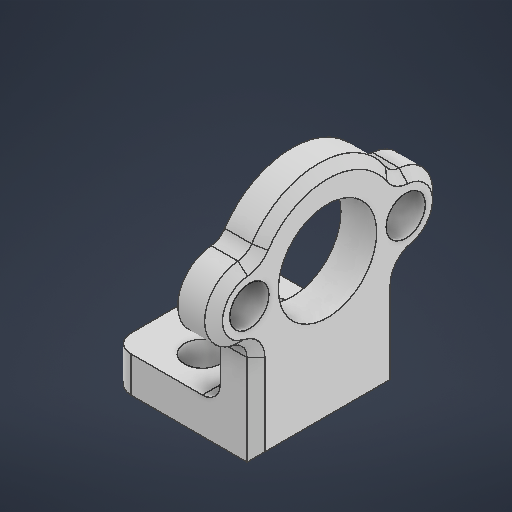
# Autodesk Inventor part: T8_holder
Saved by Autodesk Inventor 2026.2 (Build 302298010, 298A)
## iProperties
Created: 2026-04-23
Part Number: T8_holder
Material: 일반
Document SubType Name: Modeling
Designer: work
Density: 1 g/cm^3
Appearance: 기본값
Author: work
Autodesk Inventor part; units mm, degrees
ref_plane "YZ Plane" through (0, 0, 0) normal (1, 0, 0) x (0, 1, 0)
ref_plane "XZ Plane" through (0, 0, 0) normal (0, 1, 0) x (-1, 0, 0)
ref_plane "XY Plane" through (0, 0, 0) normal (0, 0, 1) x (1, 0, 0)
sketch "스케치1" plane through (0, 0, 0) normal (0, 1, 0) x (-1, 0, 0)
  line L0 (0, 4) -> (0, -4)
  circle A0 centre (0, 4) radius 2
  circle A1 centre (0, -4) radius 2
  line L1 (-6, 8) -> (6, 8)
  line L2 (6, 8) -> (6, -8)
  line L3 (6, -8) -> (-6, -8)
  line L4 (-6, -8) -> (-6, 8)
  line L5 (-6, 8) -> (6, -8) construction
  line L6 (6, 8) -> (-6, -8) construction
  point P0 (0, 0)
  dimension "d0" = 8
  dimension "d1" = 4
  dimension "d2" = 4
  dimension "d3" = 12
  dimension "d4" = 16
  constraints: 14 end point, 3 midpoint, 2 centre point, 2 coincident, 2 parallel, 1 horizontal, 1 perpendicular, 1 vertical
  measures "d0" distance of L0.start L0.end
  measures "d1" diameter of A0
  measures "d2" diameter of A1
  measures "d3" distance of L2.end L3.end
  measures "d4" distance of L1.end L2.end
extrude "돌출1" add sketch "스케치1" along normal blind 4
sketch "스케치2" plane through (6, 0, 8) normal (1, 0, 0) x (0, 0, -1)
  line L0 (16, 0) -> (0, 0) projected
  line L1 (0, 0) -> (16, 0)
  line L2 (16, 0) -> (16, 20) construction
  line L3 (16, 20) -> (0, 20) construction
  line L4 (0, 20) -> (0, 0) construction
  line L5 (8, 0) -> (8, 16) construction
  circle A0 centre (8, 16) radius 5.5
  line L6 (-0.75, 16) -> (16.75, 16) construction
  circle A1 centre (-0.75, 16) radius 2.2
  circle A2 centre (16.75, 16) radius 2.2
  arc A3 (16, 20) -> (0, 20) centre (8, 16) ccw
  line L7 (-0.75, 16) -> (16.75, 16) construction
  line L8 (-0.75, 12) -> (16.75, 12)
  line L9 (16.75, 20) -> (-0.75, 20)
  arc A4 (-0.75, 20) -> (-0.75, 12) centre (-0.75, 16) ccw
  arc A5 (16.75, 12) -> (16.75, 20) centre (16.75, 16) ccw
  line L10 (0, 12) -> (0, 0)
  line L11 (16, 12) -> (16, 0)
  point P0 (0, 20)
  point P1 (16, 20)
  dimension "d7" = 16
  dimension "d8" = 4
  dimension "d9" = 11
  dimension "d10" = 17.5
  dimension "d11" = 4.4
  dimension "d12" = 4.4
  dimension "d13" = 4
  constraints: 24 end point, 6 centre point, 6 point on circle, 5 point on line, 4 tangent, 3 coincident, 3 collinear, 3 parallel, 2 horizontal, 2 midpoint, 1 concentric, 1 perpendicular, 1 vertical
  measures "d7" distance of L5.start L5.end
  measures "d8" distance from line of L3 L5.end
  measures "d9" diameter of A0
  measures "d10" distance of L6.start L6.end
  measures "d11" diameter of A1
  measures "d12" diameter of A2
  measures "d13" radius of A4
extrude "돌출2" add sketch "스케치2" along normal blind 4 contours L0 L10 L8 A0 L11 | L8 A0 L9 A5 | L8 A4 L9 A0 | L9 A3 A0
fillet "모깎기1" radius 2 7 edges at (-6, 2, -8) (-6, 2, 8) (6, 4, 0) (8, 20, -8) (8, 20, 8) (8, 12, 8) (8, 12, -8)
chamfer "모따기1" distance 1 angle 45 8 edges at (10, 5.0658, -8) (10, 16.282, -12.74) (10, 20.2606, -8.1505) (10, 24.9443, 0) (10, 20.2606, 8.1505) (10, 16.282, 12.74) (10, 5.0658, 8) (10, 0, 0)
